Nut (Autodesk Fusion 360 design; units mm, degrees)
Autodesk Fusion 360 part; units mm, degrees
sketch "Sketch1" plane through (0, 0, 0) normal (0, 1, 0) x (1, 0, 0)
  line L0 (1.1547, -2) -> (2.3094, 0)
  line L1 (2.3094, 0) -> (1.1547, 2)
  line L2 (1.1547, 2) -> (-1.1547, 2)
  line L3 (-1.1547, 2) -> (-2.3094, 0)
  line L4 (-2.3094, 0) -> (-1.1547, -2)
  line L5 (-1.1547, -2) -> (1.1547, -2)
  circle A0 centre (0, 0) radius 1.25
  dimension "d1" = 2.5
  constraint coincident A0.centre origin
  measures "d1" diameter of A0
extrude "Extrude1" add sketch "Sketch1" along normal blind 1
thread "Thread1" "ISO Metric profile 2.5 M2.5x0.45 6H" major diameter 2.58 minor diameter 2.0755 pitch 0.45 angle 60 modelled right hand crest width 0.0563 on face at (1.2484, 0.6667, 0.0623) crest through (1.0377, -0.2531, 0)
chamfer "Chamfer1" distance 0.075 angle 45 12 edges at (0, 1, 2) (-1.7321, 1, 1) (-1.7321, 1, -1) (0, 1, -2) (1.7321, 1, -1) (1.7321, 1, 1) (1.7321, 0, 1) (0, 0, 2) (-1.7321, 0, 1) (-1.7321, 0, -1) (0, 0, -2) (1.7321, 0, -1) tangent chain off
